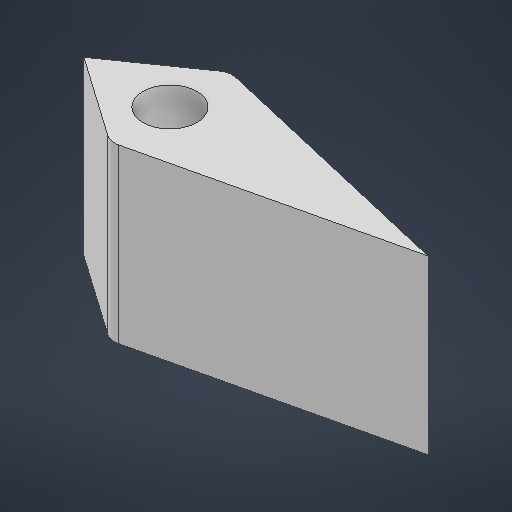
# Autodesk Inventor part: Vane 2.0
Saved by Autodesk Inventor 2026.3 (Build 303398000, 398)
## iProperties
Created: 2026-10-03
Part Number: Vane 2.0
Material: Generic
Document SubType Name: Modeling
Designer: joaqu
Density: 1 g/cm^3
Appearance: Default
Author: joaqu
Autodesk Inventor part; units mm, degrees
ref_plane "YZ Plane" through (0, 0, 0) normal (1, 0, 0) x (0, 1, 0)
ref_plane "XZ Plane" through (0, 0, 0) normal (0, 1, 0) x (-1, 0, 0)
ref_plane "XY Plane" through (0, 0, 0) normal (0, 0, 1) x (1, 0, 0)
sketch "Sketch1" plane through (0, 0, 0) normal (0, 1, 0) x (-1, 0, 0)
  line L0 (0, 0) -> (10, 0)
  line L1 (0, 0) -> (-30, 0)
  line L2 (0, 0) -> (0, -7)
  line L3 (0, -7) -> (10, 0)
  line L4 (0, -7) -> (-30, 0)
  line L5 (0, 0) -> (0, 7)
  line L6 (0, 7) -> (10, 0)
  line L7 (0, 7) -> (-30, 0)
  dimension "d0" = 10
  dimension "d1" = 30
  dimension "d2" = 7
  dimension "d3" = 7
  constraints: 16 end point, 2 horizontal, 2 vertical
  measures "d0" distance of L0.start L0.end
  measures "d1" distance of L0.start L1.end
  measures "d2" distance of L0.start L2.end
  measures "d3" distance of L0.start L5.end
extrude "Extrusion1" add sketch "Sketch1" along normal blind 20
sketch "Sketch5" plane through (0, 20, 0) normal (0, 1, 0) x (1, 0, 0)
  circle A0 centre (0, 0) radius 3.125
  dimension "d15" = 6.25
  constraints: 1 centre point, 1 coincident
  measures "d15" diameter of A0
extrude "Extrusion5" cut sketch "Sketch5" against normal up to surface (20 mm away)
sketch "Sketch6" plane through (0, 0, 0) normal (0, -1, 0) x (1, 0, 0)
  line L0 (0, 0) -> (7, 0)
  line L1 (0, 0) -> (-6.75, 0)
  line L2 (7, 0) -> (9.75, 0)
  line L3 (9.75, 0) -> (12.5, 0)
  circle A0 centre (7, 0) radius 0.75
  circle A1 centre (9.75, 0) radius 0.75
  circle A2 centre (12.5, 0) radius 0.75
  circle A3 centre (-6.75, 0) radius 0.75
  line L4 (12.5, 0) -> (15.25, 0)
  circle A4 centre (15.25, 0) radius 0.75
  dimension "d18" = 7
  dimension "d19" = 6.75
  dimension "d20" = 2.75
  dimension "d21" = 2.75
  dimension "d22" = 1.5
  dimension "d23" = 1.5
  dimension "d24" = 1.5
  dimension "d27" = 1.5
  dimension "d28" = 2.75
  dimension "d29" = 1.5
  constraints: 10 end point, 5 centre point, 5 coincident, 5 horizontal
  measures "d18" distance of L0.start L0.end
  measures "d19" distance of L0.start L1.end
  measures "d20" distance of L0.end L2.end
  measures "d21" distance of L2.end L3.end
  measures "d22" diameter of A0
  measures "d23" diameter of A1
  measures "d24" diameter of A2
  measures "d27" diameter of A3
  measures "d28" distance of L4.start L4.end
  measures "d29" diameter of A4
extrude "Extrusion6" cut sketch "Sketch6" against normal blind 6.75
fillet "Fillet1" radius 2 1 edges at (0, 10, 7)
fillet "Fillet2" radius 2 1 edges at (0, 10, -7)
equation "\"d25\" = d19"
body "Solid1"
